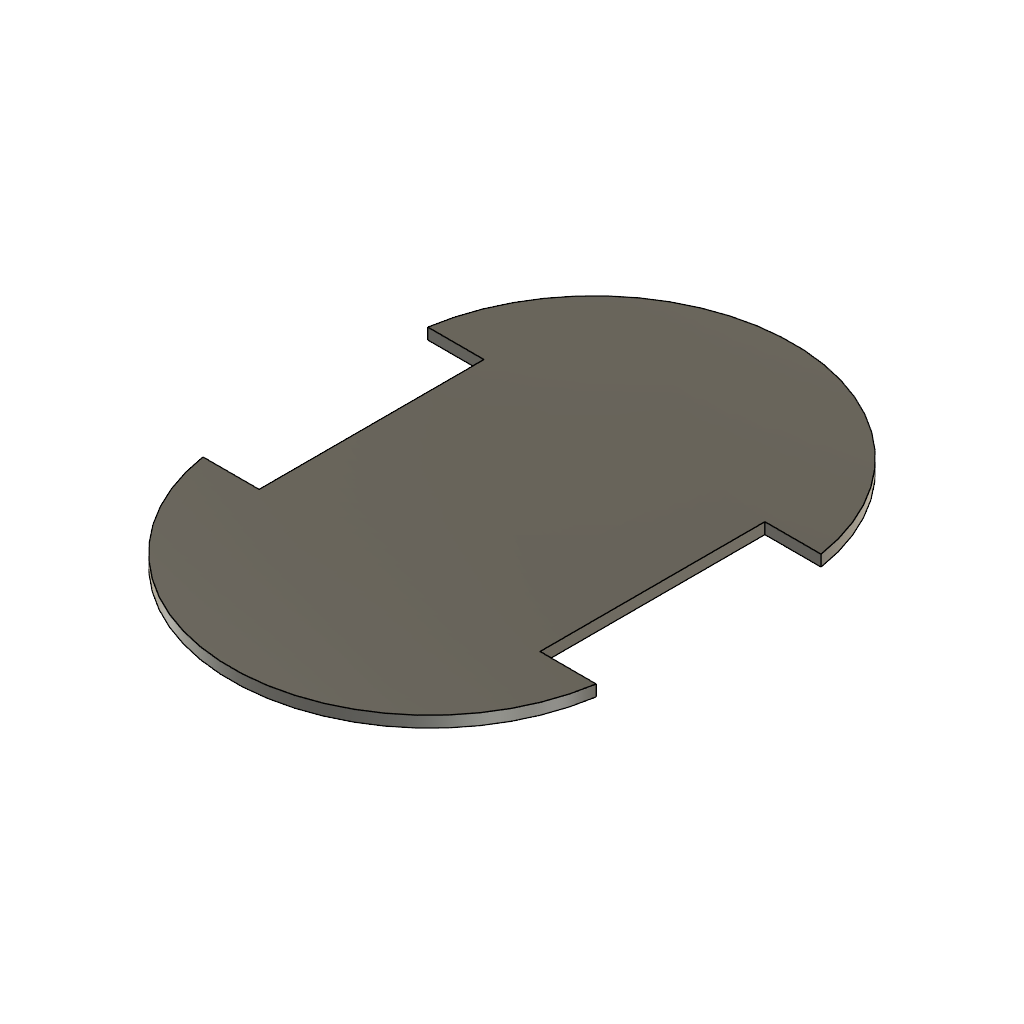
Self driving robot chassis (Autodesk Fusion 360 design; units mm, degrees)
part number: 2026-10-20-00-00-28-563
Autodesk Fusion 360 part; units mm, degrees
sketch "Sketch1" plane through (0, 0, 0) normal (0, 0, 1) x (1, 0, 0)
  line L0 (0, 0) -> (-50, 0) construction
  line L1 (0, 0) -> (0, 100) construction
  line L2 (-50, 0) -> (-50, 40)
  line L3 (-50, 40) -> (-70, 40)
  arc A0 (0, 100) -> (-70, 40) centre (0, 29.1667) ccw
  arc A1 (70, 40) -> (0, 100) centre (0, 29.1667) ccw
  line L4 (50, 40) -> (70, 40)
  line L5 (50, 0) -> (50, 40)
  arc A2 (-70, -40) -> (0, -100) centre (0, -29.1667) ccw
  arc A3 (0, -100) -> (70, -40) centre (0, -29.1667) ccw
  line L6 (50, -40) -> (70, -40)
  line L7 (50, 0) -> (50, -40)
  line L8 (-50, 0) -> (-50, -40)
  line L9 (-50, -40) -> (-70, -40)
  dimension "d1" = 50
  dimension "d2" = 40
  dimension "d3" = 20
  dimension "d4" = 100
  constraint coincident L0.start L1.start
  constraint horizontal L0
  constraint perpendicular L0 L1
  constraint perpendicular L0 L2
  constraint perpendicular L2 L3
  constraint coincident L1 A0.centre
  constraint symmetric L0.end L1 L5.start
  constraint symmetric A0.start L1 A1.end
  constraint symmetric L1 L2.end L4.start
  constraint symmetric L1 L3.end A1.start
  constraint symmetric L1 A0 A1
  constraint symmetric L2.start L0 L8.start
  constraint symmetric L0 L1.end A2.end
  constraint symmetric L0 L2.end L8.end
  constraint symmetric L0 L3.end A2.start
  constraint symmetric L0 A0 A2
  constraint symmetric L0 A1.start A3.end
  constraint symmetric L0 A1 A3
  constraint symmetric L0 L4.start L6.start
  constraint symmetric L0 L5.start L7.start
  measures "d1" distance of L0.start L0.end
  measures "d2" distance of L0.end L2.end
  measures "d3" distance of L2.end L3.end
  measures "d4" distance of L0.start L1.end
extrude "Extrude1" add sketch "Sketch1" along normal blind 4
equation "d4 = ( 200 / 2 ) * 1 mm"
